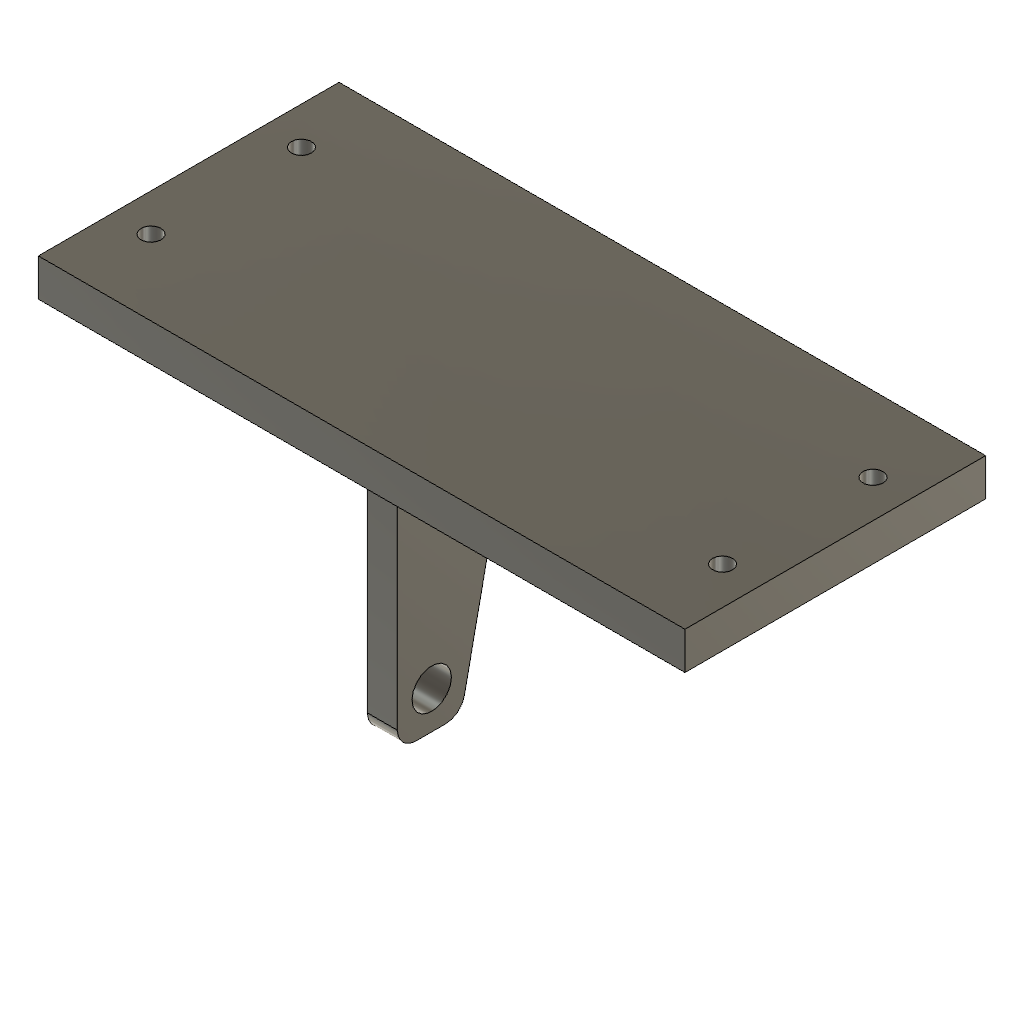
frame_top_plate (Autodesk Fusion 360 design; units mm, degrees)
part number: 2026-10-05-14-19-54-162
Autodesk Fusion 360 part; units mm, degrees
sketch "Sketch1" plane through (0, 0, 0) normal (0, 0, 1) x (1, 0, 0)
  line L0 (0, 0) -> (172, 0)
  line L1 (172, 0) -> (172, 80)
  line L2 (172, 80) -> (0, 80)
  line L3 (0, 80) -> (0, 0)
  line L4 (142, 80) -> (142, 0)
  line L5 (30, 80) -> (30, 0)
  line L6 (162, 80) -> (162, 0) construction
  line L7 (10, 0) -> (10, 80) construction
  circle A0 centre (10, 60) radius 2.65
  circle A1 centre (10, 20) radius 2.65
  circle A2 centre (162, 60) radius 2.65
  circle A3 centre (162, 20) radius 2.65
  line L8 (81, 0) -> (91, 0)
  line L9 (91, 80) -> (81, 80)
  dimension "d5" = 172
  dimension "d6" = 80
  dimension "d7" = 30
  dimension "d8" = 30
  dimension "d9" = 10
  dimension "d10" = 10
  dimension "d11" = 5.3
  dimension "d12" = 5.3
  dimension "d13" = 5.3
  dimension "d14" = 5.3
  dimension "d15" = 20
  dimension "d16" = 20
  dimension "d17" = 20
  dimension "d18" = 20
  constraint horizontal L0
  constraint vertical L1
  constraint horizontal L2
  constraint vertical L3
  constraint coincident L0.start L3.end
  constraint coincident L2 L4.start
  constraint coincident L0 L4.end
  constraint perpendicular L0 L4
  constraint coincident L2 L5.start
  constraint coincident L0 L5.end
  constraint perpendicular L0 L5
  constraint coincident L2 L6.start
  constraint coincident L0 L6.end
  constraint perpendicular L0 L6
  constraint coincident L0 L7.start
  constraint coincident L2 L7.end
  constraint perpendicular L2 L7
  constraint coincident L7 A0.centre
  constraint coincident L7 A1.centre
  constraint coincident L6 A2.centre
  constraint coincident L6 A3.centre
  constraint horizontal L8
  constraint horizontal L9
  constraint coincident L2 L9.start
  constraint coincident L0 L8.start
  measures "d5" distance of L0.start L0.end
  measures "d6" distance of L0.start L2.end
  measures "d7" distance of L3 L5
  measures "d8" distance of L1 L4
  measures "d9" distance of L1 L6
  measures "d10" distance of L3 L7
  measures "d11" diameter of A0
  measures "d12" diameter of A1
  measures "d13" diameter of A2
  measures "d14" diameter of A3
  measures "d15" distance of L2 A0.centre
  measures "d16" distance of L0 A1.centre
  measures "d17" distance of L0 A3.centre
  measures "d18" distance of L2 A2.centre
extrude "Extrude1" add sketch "Sketch1" along normal blind 10
ref_plane "WorkPlane1" through (86, 40, 5) normal (-1, 0, 0) x (0, -1, 0)
sketch "Sketch3" plane through (86, 0, 0) normal (-1, 0, 0) x (0, -1, 0)
  circle A0 centre (-14.65, -52) radius 5.25
  line L0 (-5.5, -62) -> (-22.5, -62)
  line L1 (-22.5, -62) -> (-35.5, 0)
  line L2 (-1.75, 0) -> (-22.5, 0)
  line L3 (-5.5, -62) -> (-5.5, 0)
  line L4 (-5.5, 0) -> (-35.5, 0)
  dimension "d35" = 52
  dimension "d45" = 62
  dimension "d46" = 14.65
  dimension "d47" = 10.5
  dimension "d48" = 17
  dimension "d49" = 5.5
  dimension "d50" = 30
  constraint coincident L2 L3.end
  constraint perpendicular L2 L3
  constraint perpendicular L3 L4
  constraint horizontal L0
  measures "d35" vertical distance of origin A0.centre
  measures "d45" distance of L0.start L3.end
  measures "d46" horizontal distance of origin A0.centre
  measures "d47" diameter of A0
  measures "d48" distance of L0.start L0.end
  measures "d49" distance of origin L3.end
  measures "d50" distance of L1.end L3.end
extrude "Extrude4" add sketch "Sketch3" along normal mid plane 8
fillet "Fillet3" radius 5 6 edges at (86, 5.5, -62) (86, 22.5, -62) (90, 20.5, 0) (86, 35.5, 0) (82, 20.5, 0) (86, 5.5, 0)
